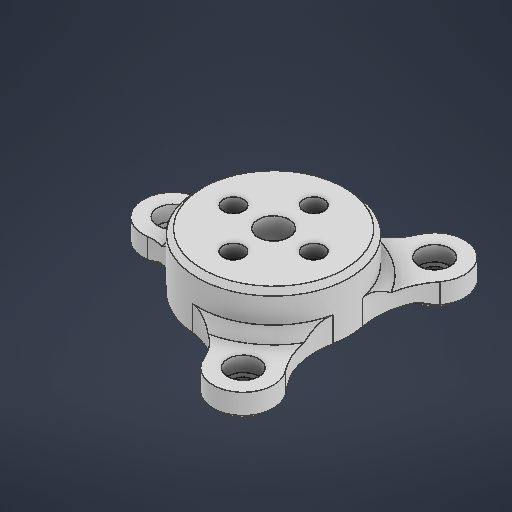
# Autodesk Inventor part: roter
Saved by Autodesk Inventor 2026.2 (Build 302298010, 298A)
## iProperties
Created: 2026-04-07
Part Number: roter
Material: 일반
Document SubType Name: Modeling
Designer: work
Density: 1 g/cm^3
Appearance: 기본값
Author: work
Autodesk Inventor part; units mm, degrees
ref_plane "YZ Plane" through (0, 0, 0) normal (1, 0, 0) x (0, 1, 0)
ref_plane "XZ Plane" through (0, 0, 0) normal (0, 1, 0) x (-1, 0, 0)
ref_plane "XY Plane" through (0, 0, 0) normal (0, 0, 1) x (1, 0, 0)
sketch "스케치1" plane through (0, 0, 0) normal (0, 1, 0) x (-1, 0, 0)
  circle A0 centre (-2, 0) radius 22 construction
  circle A1 centre (20, 0) radius 2
  line L0 (-2, 0) -> (20, 0) construction
  circle A2 centre (-13, 19.052559) radius 2
  circle A3 centre (-13, -19.052559) radius 2
  circle A4 centre (0, 0) radius 15.1
  circle A5 centre (20, 0) radius 6
  circle A6 centre (-13, -19.052559) radius 6
  arc A7 (12.190054, 8.911374) -> (19.181818, 5.943953) centre (18.171464, 13.284004) ccw
  arc A8 (19.181818, -5.943953) -> (12.190054, -8.911374) centre (18.171464, -13.284004) ccw
  line L1 (0, 0) -> (-2, 0) construction
  circle A9 centre (-13, 19.052559) radius 6
  arc A10 (-7.443295, 21.315969) -> (1.143465, 15.056643) centre (1.908104, 25.12507) ccw
  arc A11 (-14.808197, 2.954198) -> (-17.738523, 15.372016) centre (-29.859932, 5.956982) ccw
  arc A12 (1.143465, -15.056643) -> (-7.443295, -21.315969) centre (1.908104, -25.12507) ccw
  arc A13 (-17.738523, -15.372016) -> (-14.808197, -2.954198) centre (-29.859932, -5.956982) ccw
  point P0 (-14.808197, -2.954198)
  point P1 (-17.738523, -15.372016)
  point P2 (-7.443295, -21.315969)
  point P3 (12.190054, -8.911374)
  point P4 (19.181818, -5.943953)
  dimension "d10" = 12
  dimension "d1" = 44
  dimension "d2" = 4
  dimension "d5" = 360
  dimension "d7" = 30.2
  dimension "d11" = 12
  dimension "d12" = 2
  dimension "d14" = 12
  constraints: 21 point on circle, 13 centre point, 9 symmetric about line, 5 coincident, 5 tangent, 4 end point, 2 horizontal, 14 other
  measures "d1" diameter of A0
  measures "d2" diameter of A1
  measures "d7" diameter of A4
  measures "d11" diameter of A6
  measures "d12" distance of L1.start L1.end
  measures "d14" diameter of A9
extrude "돌출1" add sketch "스케치1" along normal blind 3
sketch "스케치2" plane through (0, 3, 0) normal (0, 1, 0) x (1, 0, 0)
  arc A0 (-1.143465, 15.056643) -> (-12.190054, 8.911374) centre (0, 0) ccw
  circle A1 centre (0, 0) radius 15.1
  point P0 (-1.143465, 15.056643)
  constraints: 1 coincident, 3 other
extrude "돌출2" add sketch "스케치2" along normal blind 8
sketch "스케치3" plane through (0, 0, 0) normal (0, -1, 0) x (1, 0, 0)
  arc A0 (-1.143465, 15.056643) -> (-12.190054, 8.911374) centre (0, 0) ccw
  arc A1 (-19.181818, 5.943953) -> (-12.190054, 8.911374) centre (-18.171464, 13.284004) ccw
  arc A2 (-19.181818, 5.943953) -> (-19.181818, -5.943953) centre (-20, 0) ccw
  arc A3 (-12.190054, -8.911374) -> (-19.181818, -5.943953) centre (-18.171464, -13.284004) ccw
  arc A4 (-12.190054, -8.911374) -> (-1.143465, -15.056643) centre (0, 0) ccw
  arc A5 (7.443295, -21.315969) -> (-1.143465, -15.056643) centre (-1.908104, -25.12507) ccw
  arc A6 (7.443295, -21.315969) -> (17.738523, -15.372016) centre (13, -19.052559) ccw
  arc A7 (14.808197, -2.954198) -> (17.738523, -15.372016) centre (29.859932, -5.956982) ccw
  arc A8 (14.808197, -2.954198) -> (14.808197, 2.954198) centre (0, 0) ccw
  arc A9 (17.738523, 15.372016) -> (14.808197, 2.954198) centre (29.859932, 5.956982) ccw
  arc A10 (17.738523, 15.372016) -> (7.443295, 21.315969) centre (13, 19.052559) ccw
  arc A11 (-1.143465, 15.056643) -> (7.443295, 21.315969) centre (-1.908104, 25.12507) ccw
  circle A12 centre (-20, 0) radius 2
  circle A13 centre (13, -19.052559) radius 2
  circle A14 centre (13, 19.052559) radius 2
  circle A15 centre (13, 19.052559) radius 6
  circle A16 centre (13, -19.052559) radius 6
  circle A17 centre (-20, 0) radius 6
  point P0 (17.738523, -15.372016)
  point P1 (7.443295, -21.315969)
  point P2 (7.443295, 21.315969)
  point P3 (17.738523, 15.372016)
  point P4 (-19.181818, 5.943953)
  constraints: 3 coincident, 2 centre point, 2 concentric, 3 other
extrude "돌출3" add sketch "스케치3" along normal blind 2 contours A10 A15 | A17 A2 | A6 A16
chamfer "모따기1" distance 2 angle 45 3 edges at (9.1268, 3, 12.0296) (9.1268, 3, -12.0296) (-15.1, 3, 0)
chamfer "모따기2" distance 1 angle 45 1 edges at (1.1435, 11, 15.0566)
sketch "스케치4" plane through (0, 3, 0) normal (0, 1, 0) x (1, 0, 0)
  arc A0 (17.738523, -15.372016) -> (7.443295, -21.315969) centre (13, -19.052559) ccw
  arc A1 (3.662364, -16.703206) -> (14.749968, -8.651499) centre (0, 0) ccw
  arc A2 (7.443295, -21.315969) -> (3.662364, -16.703206) centre (-1.908104, -25.12507) ccw
  arc A3 (7.443295, -21.315969) -> (17.738523, -15.372016) centre (13, -19.052559) ccw
  arc A4 (14.749968, -8.651499) -> (17.738523, -15.372016) centre (29.859932, -5.956982) ccw
  circle A5 centre (13, -19.052559) radius 2
  arc A6 (-15.927591, 6.222687) -> (-15.927591, -6.222687) centre (0, 0) ccw
  arc A7 (-19.181818, 5.943953) -> (-15.927591, 6.222687) centre (-18.171464, 13.284004) ccw
  arc A8 (-19.181818, 5.943953) -> (-19.181818, -5.943953) centre (-20, 0) ccw
  arc A9 (-15.927591, -6.222687) -> (-19.181818, -5.943953) centre (-18.171464, -13.284004) ccw
  circle A10 centre (-20, 0) radius 2
  arc A11 (14.749968, 8.651499) -> (3.662364, 16.703206) centre (0, 0) ccw
  arc A12 (17.738523, 15.372016) -> (14.749968, 8.651499) centre (29.859932, 5.956982) ccw
  arc A13 (17.738523, 15.372016) -> (7.443295, 21.315969) centre (13, 19.052559) ccw
  arc A14 (3.662364, 16.703206) -> (7.443295, 21.315969) centre (-1.908104, 25.12507) ccw
  circle A15 centre (13, 19.052559) radius 2
  constraints: 3 coincident
hole "구멍1" at (13, 3, 19.052559) at (13, 3, -19.052559) at (-20, 3, 0) direction (0, -1, 0) diameter 3.8 end through all counterbore diameter 6.2 counterbore depth 3
chamfer "모따기3" distance 1 angle 45 3 edges at (8.2615, -2, -22.7331) (-20.8182, -2, 5.944) (18.5567, -2, 16.7891)
fillet "모깎기1" radius 2 3 edges at (10, 0, 13.8564) (10, 0, -13.8564) (-14, 0, 0)
sketch "스케치5" plane through (0, 11, 0) normal (0, 1, 0) x (1, 0, 0)
  circle A0 centre (0, 0) radius 3.1
  circle A1 centre (0, 0) radius 8 construction
  circle A2 centre (0, -8) radius 2.05
  line L0 (0, 0) -> (0, -8) construction
  circle A3 centre (8, 0) radius 2.05
  circle A4 centre (0, 8) radius 2.05
  circle A5 centre (-8, 0) radius 2.05
  dimension "d39" = 16
  dimension "d38" = 6.2
  dimension "d40" = 4.1
  dimension "d43" = 360
  constraints: 5 centre point, 2 coincident, 2 end point, 1 vertical, 1 vertical alignment, 11 other
  measures "d38" diameter of A0
  measures "d40" diameter of A2
extrude "돌출4" cut sketch "스케치5" against normal through all
